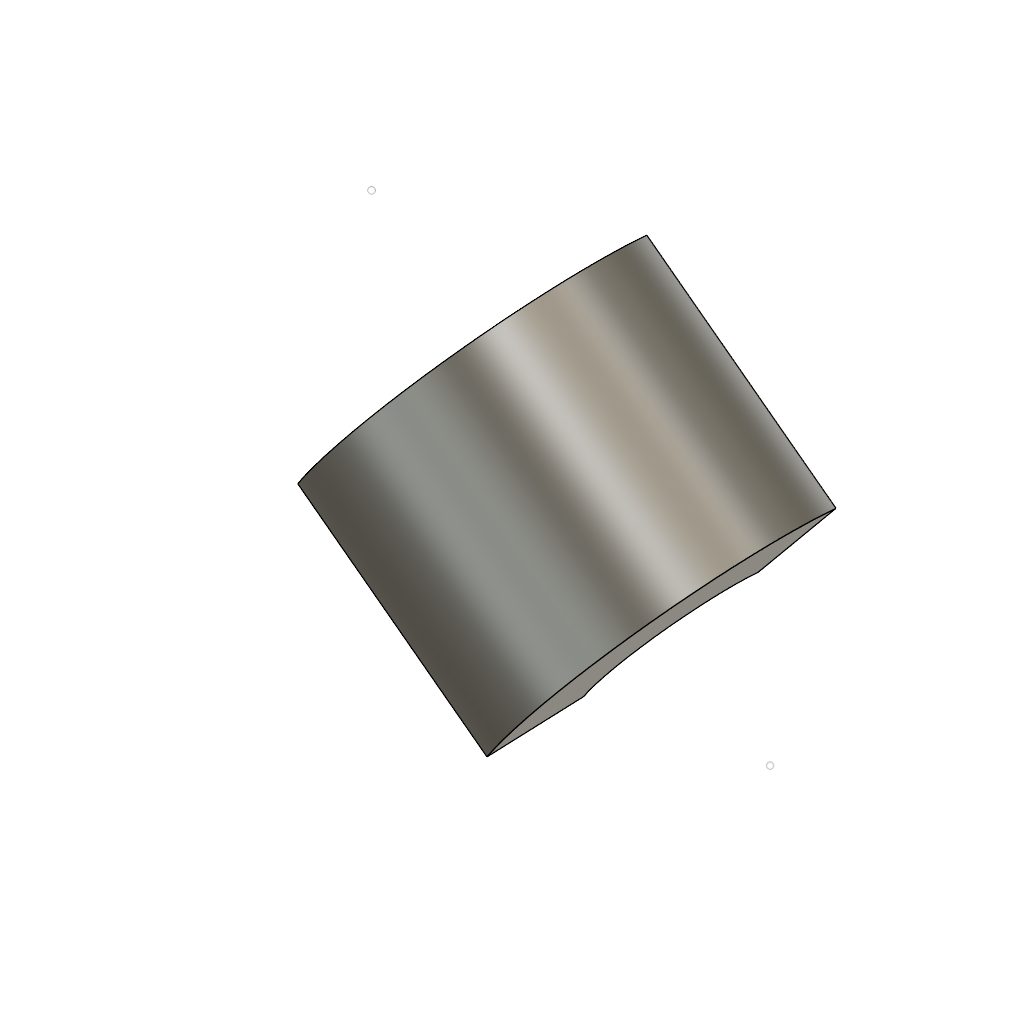
holdout_b (Autodesk Fusion 360 design; units mm, degrees)
part number: 2026-11-27-16-03-38-174
Autodesk Fusion 360 part; units mm, degrees
sketch "AxisSupport" plane through (0, 0, 0) normal (0, 0, 1) x (1, 0, 0)
  point P0 (-3, -27)
  point P1 (29, -51)
sketch "RevolveProfile" plane through (0, 0, 0) normal (0, 0, 1) x (1, 0, 0)
  line L0 (10.8, -28.6) -> (26, -40)
  line L1 (26, -40) -> (30.2, -34.4)
  line L2 (30.2, -34.4) -> (15, -23)
  line L3 (15, -23) -> (10.8, -28.6)
revolve "UnequalRevolve" add sketch "RevolveProfile" angle 103 about axis through (-9.4, -22.2, 0) along (0.8, -0.6, 0) second angle 19
